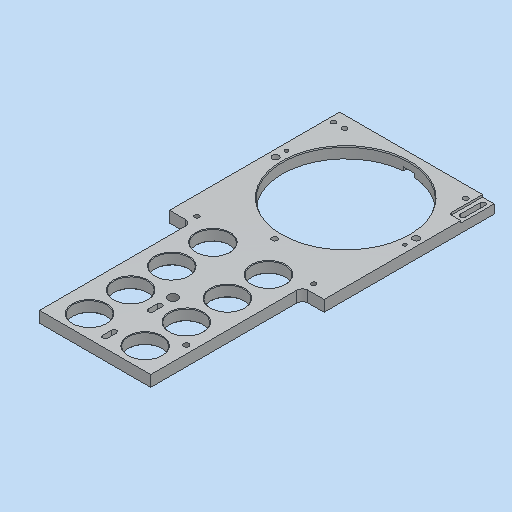
# Autodesk Inventor part: MM0948AN100_G01_109
Saved by Autodesk Inventor 2023.3 (Build 273359000, 359)
## iProperties
Part Number: MM0948AN100_G01_109
Material: 3.3547 AlMg4,5Mn0,7 - AW 5083
Description: =<RBPARTNOTITLE2>
Document SubType Name: Modeling
Designer: ric7an
Mass: 498.011 g
Surface Area: 595.518 cm^2
Volume: 184.448 cm^3
Density: 2.7 g/cm^3
Appearance: Aluminium AnP
Created: 2023-03-23
RBDOCUMENTTYPE: DRF
RBDOCUMENTVERSION: 00
RBDRAWINGMAINSCALE: 1:1
RBDRAWINGMISSINGSPEC: --
RBDRAWINGVOLUME: --
RBGBEDGESIN1: +0,5
RBGBEDGESIN2: +0,2
RBGBEDGESOUT1: -0,3
RBGBEDGESOUT2: -0,1
RBMATERIAL: =<Material>
RBMATMEETS: --
RBMATNO: =<Part Number>
RBPARTMADEOF: 10 x 279,5 x 139 (FM)
RBPARTNO: SIEHE MNR
RBPARTNOTITLE1: manufactured part
RBPARTNOTITLE2: Anfertigungsteil
RBPARTSAFETYINDICATOR: --
RBSURFACE: anodised colourless
RBSURFACE2: eloxiert farblos
RBZEDGESNORM: ISO13715:2002-06
RBZGENDIMCLASS: m
RBZGENDIMNORM: ISO 2768-1:1989-11
RBZGENGEOCLASS: H
RBZGENGEONORM: ISO 2768-2:1989-11
RBZSURFACENORM: ISO13D2:2002-02
RBZTOLERANCENORM: ISO 14405-1:2010-12
AnP_Material: =<Material>
AnP_TemplVers: 20190222
AnP_Kategorie: 1
MaxAbmaße: 10 x 279,5 x 139 (FM)
AnP_Kommentar_aktuell: =<Comments>
AnP_Material_aktuell: =<Material>
Author: FH/Wi
Keywords: =<RBPARTMADEOF>
Comments: =<RBSURFACE2>
Revision Number: 01
Autodesk Inventor part; units mm, degrees
ref_plane "YZ Plane" through (0, 0, 0) normal (1, 0, 0) x (0, 1, 0)
ref_plane "XZ Plane" through (0, 0, 0) normal (0, 1, 0) x (-1, 0, 0)
ref_plane "XY Plane" through (0, 0, 0) normal (0, 0, 1) x (1, 0, 0)
sketch "Skizze1" plane through (0, 0, 0) normal (0, 0, 1) x (1, 0, 0)
  line L0 (-69.5, 144.75) -> (69.5, 144.75)
  line L1 (69.5, 144.75) -> (69.5, -144.75)
  line L2 (69.5, -144.75) -> (-69.5, -144.75)
  line L3 (-69.5, -144.75) -> (-69.5, 144.75)
  line L4 (0, 202.65) -> (0, -202.65) projected
  line L5 (-97.3, 0) -> (97.3, 0) projected
  point P0 (0, 0)
  dimension "d0" = 289.5
  dimension "d1" = 139
  constraints: 8 end point, 2 parallel, 1 horizontal, 1 perpendicular, 2 other
  measures "d0" distance of L0.end L1.end
  measures "d1" distance of L0.start L0.end
extrude "Extrusion1" add sketch "Skizze1" along normal blind 10
sketch "Skizze4" plane through (0, 0, 10) normal (0, 0, 1) x (1, 0, 0)
  line L0 (69.5, 144.75) -> (-69.5, 144.75) projected
  line L1 (-69.5, 144.75) -> (-69.5, -144.75) projected
  line L2 (-69.5, -144.75) -> (69.5, -144.75) projected
  line L3 (69.5, -144.75) -> (69.5, 144.75) projected
  line L4 (-69.5, -144.75) -> (-50, -144.75)
  line L5 (-50, -144.75) -> (-50, -8.25)
  line L6 (-50, -8.25) -> (-69.5, -8.25)
  line L7 (-69.5, -8.25) -> (-69.5, -144.75)
  line L8 (69.5, -144.75) -> (50, -144.75)
  line L9 (50, -144.75) -> (50, -8.25)
  line L10 (50, -8.25) -> (69.5, -8.25)
  line L11 (69.5, -8.25) -> (69.5, -144.75)
  line L12 (0, 202.65) -> (0, -202.65) projected
  line L13 (-97.3, 0) -> (97.3, 0) projected
  line L14 (-69.5, 144.75) -> (-69.5, -144.75) projected
  line L15 (69.5, -144.75) -> (69.5, 144.75) projected
  point P0 (0, 0)
  dimension "d105" = 100
  dimension "d290" = 153
  constraints: 16 end point, 4 parallel, 2 horizontal, 2 perpendicular, 1 point on line, 1 other
  measures "d105" distance between parallel lines of L9 L5
  measures "d290" distance between parallel lines of L6 L0
extrude "Extrusion3" cut sketch "Skizze4" against normal through all contours L3 L2 L9 L10 | L6 L5 L2 L1
sketch "Skizze8" plane through (0, 0, 0) normal (1, 0, 0) x (0, 1, 0)
  line L0 (-144.75, 10) -> (144.75, 10) projected
  line L1 (144.75, 0) -> (-144.75, 0) projected
  line L2 (80.75, 10) -> (80.75, 0) construction
  line L3 (-144.75, 0) -> (-144.75, 10) projected
  line L4 (80.75, 0) -> (-0.8044, 0)
  line L5 (3.8064, 10) -> (80.75, 10)
  line L6 (80.75, 10) -> (80.75, 0)
  line L7 (80.75, 0) -> (-0.8044, 0)
  line L8 (23.2837, 10) -> (23.75, 9)
  line L9 (23.75, 9) -> (23.75, 0)
  line L10 (144.75, 0) -> (144.75, 10) projected
  dimension "d265" = 57
  dimension "d266" = 25
  dimension "d268" = 1
  dimension "d291" = 64
  constraints: 14 end point, 5 point on line, 3 collinear, 2 perpendicular
  measures "d265" distance between parallel lines of L2 L9
  measures "d266" angle of L9 L8
  measures "d268" vertical distance of L8.end L8.start
  measures "d291" distance between parallel lines of L10 L2
revolve "Umdrehung2" cut sketch "Skizze8" angle 360 about axis through (0, 80.75, 10) along (0, 0, -1) contours L0 L6 L1 L9 L8
sketch "Skizze9" plane through (0, 0, 10) normal (0, 0, 1) x (1, 0, 0)
  line L0 (0, 202.65) -> (0, -202.65) projected
  line L1 (-97.3, 0) -> (97.3, 0) projected
  circle A0 centre (0, 80.75) radius 57 projected
  point P0 (0, 0)
  point P1 (0, 16.75)
  dimension "d146" = 64
  constraints: 1 coincident, 1 point on line
  measures "d146" distance of point (0, 16.75) point (0, 80.75)
hole "Bohrung6" at (0, 16.75, 10) direction (0, 0, -1) diameter 4.8 end through all counterbore diameter 5 counterbore depth 7
sketch "Skizze11" plane through (0, 0, 10) normal (0, 0, 1) x (1, 0, 0)
  line L0 (0, 202.65) -> (0, -202.65) projected
  line L1 (-97.3, 0) -> (97.3, 0) projected
  line L2 (-69.5, -144.75) -> (69.5, -144.75) projected
  point P0 (0, 0)
  point P1 (-25, -87.75)
  point P2 (25, -87.75)
  point P3 (25, -124.75)
  point P4 (-25, -124.75)
  point P5 (-50, -144.75)
  point P6 (50, -144.75)
  point P7 (-25, -50.75)
  point P8 (25, -50.75)
  point P9 (0, -69.25)
  point P10 (0, -109.75)
  point P11 (-25, -13.75)
  point P12 (25, -13.75)
  dimension "d106" = 50
  dimension "d107" = 20
  dimension "d108" = 37
  dimension "d173" = 37
  dimension "d174" = 18.5
  dimension "d182" = 15
  dimension "d201" = 37
  dimension "d202" = 50
  constraints: 3 symmetric about line, 3 vertical alignment, 2 point on line, 1 horizontal alignment
  measures "d106" distance of point (25, -124.75) point (-25, -124.75)
  measures "d107" distance from line of L2 point (25, -124.75)
  measures "d108" distance of point (25, -124.75) point (25, -87.75)
  measures "d173" distance of point (25, -87.75) point (25, -50.75)
  measures "d174" vertical distance of point (25, -87.75) point (0, -69.25)
  measures "d182" vertical distance of point (25, -124.75) point (0, -109.75)
  measures "d201" distance of point (25, -13.75) point (25, -50.75)
  measures "d202" distance of point (25, -13.75) point (-25, -13.75)
hole "Bohrung8" at (-25, -87.75, 10) at (25, -87.75, 10) at (25, -124.75, 10) at (-25, -124.75, 10) at (-25, -50.75, 10) at (25, -50.75, 10) at (-25, -13.75, 10) at (25, -13.75, 10) direction (0, 0, -1) diameter 30 end through all
sketch "Skizze19" plane through (0, 0, 10) normal (0, 0, 1) x (1, 0, 0)
  line L0 (64.5, 139.5) -> (64.5, 121.5) construction
  line L1 (62.25, 139.5) -> (62.25, 121.5)
  line L2 (66.75, 121.5) -> (66.75, 139.5)
  arc A0 (66.75, 139.5) -> (62.25, 139.5) centre (64.5, 139.5) ccw
  arc A1 (62.25, 121.5) -> (66.75, 121.5) centre (64.5, 121.5) ccw
  line L3 (69.5, 144.75) -> (69.5, -8.25) projected
  line L4 (69.5, -8.25) -> (69.5, 144.75) projected
  line L5 (-69.5, 144.75) -> (69.5, 144.75) projected
  line L6 (69.5, 144.75) -> (-69.5, 144.75) projected
  point P0 (0, 0)
  point P1 (64.5, 130.5)
  dimension "d220" = 5
  dimension "d221" = 18
  dimension "d222" = 5.25
  dimension "d225" = 4.5
  constraints: 8 end point, 4 point on circle, 4 tangent, 2 centre point, 1 midpoint, 1 parallel, 1 vertical
  measures "d220" distance between parallel lines of L3 L0
  measures "d221" distance of L0.end L0.start
  measures "d222" distance from line of L5 L0.start
  measures "d225" distance between parallel lines of L2 L1
extrude "Extrusion5" cut sketch "Skizze19" against normal through all
sketch "Skizze20" plane through (0, 0, 0) normal (0, 0, -1) x (-1, 0, 0)
  arc A0 (-62.25, 139.5) -> (-66.75, 139.5) centre (-64.5, 139.5) ccw projected
  arc A1 (-66.75, 121.5) -> (-62.25, 121.5) centre (-64.5, 121.5) ccw projected
  line L0 (-62.25, 139.5) -> (-62.25, 121.5) projected
  line L1 (-66.75, 121.5) -> (-66.75, 139.5) projected
  line L2 (-64.5, 139.5) -> (-64.5, 121.5) construction
  line L3 (-67.5, 139.5) -> (-67.5, 121.5)
  line L4 (-61.5, 121.5) -> (-61.5, 139.5)
  arc A2 (-61.5, 139.5) -> (-67.5, 139.5) centre (-64.5, 139.5) ccw
  arc A3 (-67.5, 121.5) -> (-61.5, 121.5) centre (-64.5, 121.5) ccw
  point P0 (0, 0)
  point P1 (-64.5, 130.5)
  dimension "d226" = 6
  constraints: 8 end point, 4 point on circle, 4 tangent, 2 centre point, 1 coincident, 1 midpoint, 1 parallel, 1 vertical
  measures "d226" distance between parallel lines of L3 L4
extrude "Extrusion6" cut sketch "Skizze20" against normal blind 3 contours L0 A1 L1 A0 | A2 L4 A3 L3
sketch "Skizze22" plane through (0, 0, 10) normal (0, 0, 1) x (1, 0, 0)
  line L0 (62.25, 121.5) -> (62.25, 139.5) projected
  arc A0 (66.75, 139.5) -> (62.25, 139.5) centre (64.5, 139.5) ccw projected
  line L1 (66.75, 139.5) -> (66.75, 121.5) projected
  arc A1 (62.25, 121.5) -> (66.75, 121.5) centre (64.5, 121.5) ccw projected
  line L2 (59, 144.75) -> (59, 116.75)
  line L3 (69.5, 144.75) -> (69.5, -8.25) projected
  line L4 (69.5, -8.25) -> (69.5, 144.75) projected
  line L5 (-69.5, 144.75) -> (69.5, 144.75) projected
  line L6 (69.5, 144.75) -> (-69.5, 144.75) projected
  line L7 (61, 114.75) -> (69.5, 114.75)
  line L8 (69.5, 144.75) -> (-69.5, 144.75) projected
  line L9 (64.5, 139.5) -> (64.5, 121.5) construction
  line L10 (60, 139.5) -> (60, 121.5) construction
  line L11 (69, 121.5) -> (69, 139.5) construction
  arc A2 (69, 139.5) -> (60, 139.5) centre (64.5, 139.5) ccw construction
  arc A3 (60, 121.5) -> (69, 121.5) centre (64.5, 121.5) ccw construction
  arc A4 (59, 116.75) -> (61, 114.75) centre (61, 116.75) ccw
  point P0 (0, 0)
  point P1 (64.5, 130.5)
  point P2 (59, 144.75)
  dimension "d231" = 10.5
  dimension "d233" = 9
  dimension "d234" = 2
  dimension "d269" = 30
  constraints: 12 end point, 6 point on circle, 6 tangent, 3 centre point, 2 parallel, 2 point on line, 1 midpoint, 1 perpendicular
  measures "d231" distance between parallel lines of L3 L2
  measures "d233" distance between parallel lines of L11 L10
  measures "d234" radius of A4
  measures "d269" distance between parallel lines of L5 L7
extrude "Extrusion7" cut sketch "Skizze22" against normal blind 2 contours L0 A0 L1 A1 | L5 L3 L7 A4 L2
sketch "Skizze17" plane through (0, 0, 10) normal (0, 0, 1) x (1, 0, 0)
  line L0 (0, 202.65) -> (0, -202.65) projected
  line L1 (-69.5, -8.25) -> (-50, -8.25) projected
  point P0 (0, 0)
  point P1 (-52.5, -0.75)
  point P2 (52.5, -0.75)
  dimension "d192" = 7.5
  dimension "d193" = 105
  constraints: 1 symmetric about line
  measures "d192" distance from line of L1 point (-52.5, -0.75)
  measures "d193" distance of point (52.5, -0.75) point (-52.5, -0.75)
hole "Bohrung16" at (-52.5, -0.75, 10) at (52.5, -0.75, 10) direction (0, 0, -1) diameter 4.134 end through all thread size "M5x0.8" designation "M5" class "6H" standard "ISO Metric profile"
chamfer "Fase3" distance 0.5 angle 45 16 edges at (-25, -35.75, 10) (25, -35.75, 10) (25, -72.75, 10) (-25, -72.75, 10) (25, -109.75, 10) (-25, -109.75, 10) (25, -35.75, 0) (-25, -35.75, 0) (25, -72.75, 0) (25, -109.75, 0) (-25, -72.75, 0) (-25, -109.75, 0) (-25, 1.25, 10) (-25, 1.25, 0) (25, 1.25, 10) (25, 1.25, 0)
fillet "Rundung1" radius 5 2 edges at (-50, -8.25, 5) (50, -8.25, 5)
sketch "Skizze18" plane through (0, 0, 0) normal (0, 0, 1) x (1, 0, 0)
  line L0 (0, 202.65) -> (0, -202.65) projected
  line L1 (59, 144.75) -> (-69.5, 144.75) projected
  point P0 (0, 0)
  point P1 (-54.5, 134.25)
  point P2 (54.5, 134.25)
  point P3 (-64.5, 134.25)
  dimension "d208" = 109
  dimension "d209" = 10.5
  dimension "d311" = 10
  constraints: 1 horizontal alignment, 1 symmetric about line
  measures "d208" distance of point (54.5, 134.25) point (-54.5, 134.25)
  measures "d209" distance from line of L1 point (54.5, 134.25)
  measures "d311" distance of point (-54.5, 134.25) point (-64.5, 134.25)
hole "Bohrung17" at (-54.5, 134.25, 0) at (54.5, 134.25, 0) at (-64.5, 134.25, 0) direction (0, 0, 1) diameter 4.5 end through all counterbore diameter 8 counterbore depth 4.6 clearance for "Inbusschraube ISO 4762  versenkt" size "M4" standard "ISO"
sketch "Skizze23" plane through (0, 0, 10) normal (0, 0, 1) x (1, 0, 0)
  line L0 (0, -86.75) -> (0, -94.75) construction
  line L1 (-2.25, -86.75) -> (-2.25, -94.75)
  line L2 (2.25, -94.75) -> (2.25, -86.75)
  arc A0 (2.25, -86.75) -> (-2.25, -86.75) centre (0, -86.75) ccw
  arc A1 (-2.25, -94.75) -> (2.25, -94.75) centre (0, -94.75) ccw
  line L3 (0, 202.65) -> (0, -202.65) projected
  line L4 (0, -127.75) -> (0, -135.75) construction
  line L5 (-2.25, -127.75) -> (-2.25, -135.75)
  line L6 (2.25, -135.75) -> (2.25, -127.75)
  arc A2 (2.25, -127.75) -> (-2.25, -127.75) centre (0, -127.75) ccw
  arc A3 (-2.25, -135.75) -> (2.25, -135.75) centre (0, -135.75) ccw
  line L7 (-50, -144.75) -> (50, -144.75) projected
  line L8 (50, -144.75) -> (-50, -144.75) projected
  point P0 (0, 0)
  point P1 (0, -90.75)
  point P2 (0, -131.75)
  point P3 (-38.379, -144.75)
  point P4 (-41.621, -144.75)
  point P5 (41.621, -144.75)
  point P6 (38.379, -144.75)
  dimension "d237" = 4.5
  dimension "d238" = 8
  dimension "d239" = 4.5
  dimension "d240" = 8
  dimension "d241" = 41
  dimension "d292" = 13
  constraints: 16 end point, 8 point on circle, 8 tangent, 4 centre point, 3 point on line, 2 collinear, 2 midpoint, 2 parallel, 2 vertical, 1 coincident
  measures "d237" distance between parallel lines of L2 L1
  measures "d238" distance of L0.end L0.start
  measures "d239" distance between parallel lines of L6 L5
  measures "d240" distance of L4.end L4.start
  measures "d241" distance of point (0, -90.75) point (0, -131.75)
  measures "d292" distance from line of L7 point (0, -131.75)
extrude "Extrusion8" cut sketch "Skizze23" against normal through all
chamfer "Fase5" distance 0.5 angle 45 4 edges at (61.5, 130.5, 0) (64.5, 118.5, 0) (67.5, 130.5, 0) (64.5, 142.5, 0)
sketch "Skizze24" plane through (0, 0, 10) normal (0, 0, 1) x (1, 0, 0)
  line L0 (0, 202.65) -> (0, -202.65) projected
  line L1 (-69.5, 144.75) -> (-69.5, -8.25) projected
  line L2 (-50, -144.75) -> (50, -144.75) projected
  circle A0 centre (0, 80.75) radius 57.4663 projected
  point P0 (0, 0)
  point P1 (-63.25, 80.75)
  point P2 (63.25, 80.75)
  dimension "d248" = 6.25
  constraints: 1 horizontal alignment, 1 symmetric about line
  measures "d248" distance from line of L1 point (-63.25, 80.75)
hole "Bohrung18" at (-63.25, 80.75, 10) at (63.25, 80.75, 10) direction (0, 0, -1) diameter 6 end through all
sketch "Skizze25" plane through (0, 0, 10) normal (0, 0, 1) x (1, 0, 0)
  circle A0 centre (-63.25, 80.75) radius 3 projected
  circle A1 centre (63.25, 80.75) radius 3 projected
  point P0 (0, 0)
  point P1 (-63.25, 90.75)
  point P2 (63.25, 70.75)
  dimension "d256" = 10
  dimension "d257" = 10
  constraints: 2 vertical alignment
  measures "d256" distance of point (63.25, 70.75) A1.centre
  measures "d257" distance of A0.centre point (-63.25, 90.75)
hole "Bohrung19" at (-63.25, 90.75, 10) at (63.25, 70.75, 10) direction (0, 0, -1) diameter 3.242 end through all thread size "M4x0.7" designation "M4" class "6H" standard "ISO Metric profile"
sketch "Skizze27" plane through (0, 0, 10) normal (0, 0, 1) x (1, 0, 0)
  line L0 (-50, -144.75) -> (50, -144.75) projected
  point P0 (0, 0)
  point P1 (0, -74.75)
  point P2 (0, -144.75)
  dimension "d288" = 70
  constraints: 1 midpoint, 1 vertical alignment
  measures "d288" distance from line of L0 point (0, -74.75)
hole "Bohrung21" at (0, -74.75, 10) direction (0, 0, -1) diameter 8.9175 end through all thread size "M10x1" class "6H" standard "ISO Metric profile"
sketch "Skizze28" plane through (-69.5, 144.75, 0) normal (0, 1, 0) x (1, 0, 0)
  line L0 (0, 0) -> (139, 0) projected
  line L1 (69.5, 2) -> (69.5, -12) projected
  point P0 (69.5, 0)
  point P1 (117, -5)
  point P2 (22, -5)
  dimension "d293" = 95
  dimension "d294" = 5
  constraints: 1 symmetric about line
  measures "d293" distance of point (22, -5) point (117, -5)
  measures "d294" distance from line of L0 point (22, -5)
hole "Bohrung22" at (47.5, 144.75, 5) at (-47.5, 144.75, 5) direction (0, -1, 0) diameter 3.242 depth 11.8 tip angle 118 thread size "M4x0.7" designation "M4" class "6H" standard "ISO Metric profile"
sketch "Skizze29" plane through (0, 0, 10) normal (0, 0, 1) x (1, 0, 0)
  line L0 (50, -144.75) -> (50, -13.25) projected
  line L1 (-50, -144.75) -> (50, -144.75) projected
  point P0 (0, 0)
  point P1 (43, -105.75)
  dimension "d302" = 7
  dimension "d303" = 39
  measures "d302" distance from line of L0 point (43, -105.75)
  measures "d303" distance from line of L1 point (43, -105.75)
hole "Bohrung23" at (43, -105.75, 10) direction (0, 0, -1) diameter 4.917 end through all thread size "M6x1" designation "M6" class "6H" standard "ISO Metric profile"
sketch "Skizze30" plane through (-69.5, 144.75, 0) normal (0, 1, 0) x (1, 0, 0)
  circle A0 centre (117, -5) radius 1.621 projected
  circle A1 centre (22, -5) radius 1.621 projected
  line L0 (128.5, -10) -> (128.5, -8) projected
  line L1 (128.5, -8) -> (139, -8) projected
  line L2 (139, 0) -> (139, -8) projected
  line L3 (0, 0) -> (139, 0) projected
  line L4 (0, 0) -> (0, -10) projected
  line L5 (128.5, -10) -> (0, -10) projected
  line L6 (74.5, 0) -> (64.5, 0)
  line L7 (64.5, 0) -> (64.5, -3)
  line L8 (64.5, -3) -> (74.5, -3)
  line L9 (74.5, -3) -> (74.5, 0)
  line L10 (69.5, 2) -> (69.5, -12) projected
  point P0 (69.5, 0)
  dimension "d312" = 10
  dimension "d313" = 3
  constraints: 8 end point, 2 parallel, 1 horizontal, 1 perpendicular, 1 point on line, 1 other
  measures "d312" distance of L7.end L8.end
  measures "d313" distance of L6.end L7.end
extrude "Extrusion9" cut sketch "Skizze30" against normal up to surface contours L10 L3 L9 L8 | L8 L7 L3 L10 round surface about axis through (0, 80.75, 4.5) along (0, 0, 1) radius 57 far side no
equation "\"d173\" = d108"
equation "\"d174\" = 0.5 * d108"
